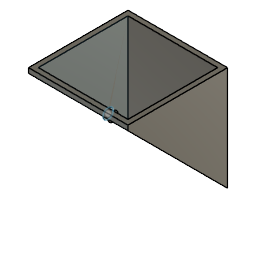
PDP_Lamp_Mid_Link (Autodesk Fusion 360 design; units mm, degrees)
Autodesk Fusion 360 part; units mm, degrees
sketch "Sketch1" plane through (0, 0, 0) normal (0, 0, 1) x (1, 0, 0)
  line L0 (-100, 100) -> (100, 100)
  line L1 (100, 100) -> (100, -100)
  line L2 (100, -100) -> (-100, -100)
  line L3 (-100, -100) -> (-100, 100)
  line L4 (-100, 100) -> (100, -100) construction
  line L5 (100, 100) -> (-100, -100) construction
  line L6 (90, -90) -> (-90, -90)
  line L7 (-90, -90) -> (-90, 90)
  line L8 (-90, 90) -> (90, 90)
  line L9 (90, 90) -> (90, -90)
  dimension "d1" = 200
  dimension "d2" = 200
  dimension "d3" = 10
  constraint horizontal L0
  constraint perpendicular L0 L1
  constraint parallel L0 L2
  constraint parallel L1 L3
  constraint coincident L4 origin
  constraint coincident L5 origin
  measures "d1" distance of L1.end L2.end
  measures "d2" distance of L0.end L1.end
extrude "Extrude1" add sketch "Sketch1" along normal blind 210
ref_plane "WorkPlane3" through (0, 100, 0) normal (0, 0.707107, 0.707107) x (1, 0, 0)
sketch "Sketch3" plane through (0, 50, 50) normal (0, 0.707107, 0.707107) x (1, 0, 0)
  line L0 (125, -225) -> (-140.5634, -225)
  line L1 (-140.5634, -225) -> (-140.5634, 124.3423)
  line L2 (-140.5634, 124.3423) -> (125, 124.3423)
  line L3 (125, 124.3423) -> (125, -225)
  constraint horizontal L0
  constraint vertical L1
  constraint horizontal L2
  constraint vertical L3
extrude "Extrude2" cut sketch "Sketch3" against normal blind 150
sketch "Sketch5" plane through (-90, 0, 0) normal (1, 0, 0) x (0, 1, 0)
  line L0 (-90, 190) -> (90, 10)
  line L1 (90, 10) -> (90, 210)
  line L2 (90, 210) -> (-90, 210)
  line L3 (-90, 210) -> (-90, 190)
  circle A0 centre (50, 60) radius 10
  dimension "d13" = 20
  measures "d13" diameter of A0
extrude "Extrude3" add sketch "Sketch5" along normal blind 10 contours L0 A0 | L0 A0
equation "d1 = d2"
